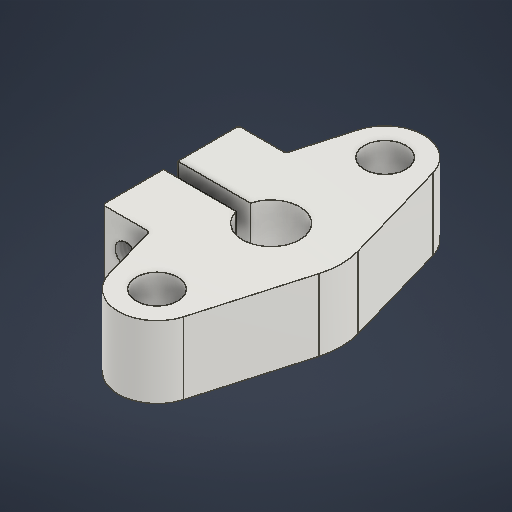
# Autodesk Inventor part: 8PI ShaftEnd Holder
Saved by Autodesk Inventor 2026.2 (Build 302298010, 298A)
## iProperties
Created: 2026-05-07
Part Number: 8PI ShaftEnd Holder
Material: 강철, 가공됨
Document SubType Name: Modeling
Designer: work
Density: 7.85 g/cm^3
Appearance: 강철
Author: work
Autodesk Inventor part; units mm, degrees
ref_plane "YZ Plane" through (0, 0, 0) normal (1, 0, 0) x (0, 1, 0)
ref_plane "XZ Plane" through (0, 0, 0) normal (0, 1, 0) x (-1, 0, 0)
ref_plane "XY Plane" through (0, 0, 0) normal (0, 0, 1) x (1, 0, 0)
sketch "스케치1" plane through (0, 0, 0) normal (0, 1, 0) x (-1, 0, 0)
  circle A0 centre (0, 0) radius 4
  line L0 (14, 9.5) -> (0, 9.5)
  line L1 (0, 9.5) -> (0, -9.5) construction
  line L2 (0, -9.5) -> (14, -9.5)
  line L3 (14, -9.5) -> (14, 9.5)
  line L4 (0, 0) -> (14, 0) construction
  line L5 (14, -1) -> (0, -1)
  line L6 (0, -1) -> (0, 1)
  line L7 (0, 1) -> (14, 1)
  line L8 (14, 1) -> (14, -1)
  line L9 (0, 0) -> (0, -15.9) construction
  circle A1 centre (0, -15.9) radius 2.9
  circle A2 centre (0, -15.9) radius 5.4
  circle A3 centre (0, 0) radius 9.8
  line L10 (-9.4173, -2.7119) -> (-5.1891, -17.3943)
  line L11 (9.4173, -2.7119) -> (5.1891, -17.3943)
  line L12 (0, 0) -> (0, 15.9) construction
  circle A4 centre (0, 15.9) radius 2.9
  circle A5 centre (0, 15.9) radius 5.4
  line L13 (-9.4173, 2.7119) -> (-5.1891, 17.3943)
  line L14 (9.4173, 2.7119) -> (5.1891, 17.3943)
  point P0 (3.873, -1)
  point P1 (3.873, 1)
  point P2 (7.4625, 9.5)
  point P3 (7.4625, -9.5)
  dimension "d0" = 8
  dimension "d1" = 19
  dimension "d2" = 10
  dimension "d3" = 2
  dimension "d4" = 5.8
  dimension "d5" = 2.5
  dimension "d6" = 5.8
  dimension "d7" = 26
  constraints: 30 end point, 9 symmetric about line, 7 coincident, 4 midpoint, 4 parallel, 3 centre point, 3 horizontal, 2 perpendicular, 1 vertical, 12 other
  measures "d0" diameter of A0
  measures "d1" distance of L1.end L0.end
  measures "d2" distance edge to line of A0 L3
  measures "d3" distance of L5.end L6.end
  measures "d4" diameter of A1
extrude "돌출1" add sketch "스케치1" along normal blind 10 contours A0 L5 A3 L7 | A3 L14 L0 L3 L7 | L5 L3 L2 L11 A3 | A3 L0 L14 | L11 L2 A3 | A3 L13 A5 L14 L0 | L2 L11 A2 L10 A3 | A5 | A2 picked at (-6.323, 4.6019)
sketch "스케치2" plane through (-14, 0, 9.5) normal (0, 0, 1) x (1, 0, 0)
  line L0 (0, 0) -> (6.5375, 0) projected
  line L1 (6.5375, 0) -> (6.5375, 10) projected
  line L2 (0, 10) -> (6.5375, 10) projected
  line L3 (0, 0) -> (0, 10) projected
  line L4 (3.2688, 0) -> (3.2688, 10) construction
  circle A0 centre (3.2688, 5.6) radius 1.5
  line L5 (0, 10) -> (6.5375, 10) projected
  point P0 (14, 0)
  dimension "d10" = 3
  dimension "d11" = 4.4
  constraints: 3 midpoint, 2 end point, 1 centre point, 1 point on line
  measures "d10" diameter of A0
  measures "d11" distance of A0.centre point (3.269, 10)
extrude "돌출2" cut sketch "스케치2" against normal through all contours A0
thread "스레드1" size "M3x0.5" class "6H" standard "ANSI Metric M Profile" full length
chamfer "모따기1" distance 0.25 angle 45 4 edges at (-7.4625, 5, 9.5) (-14, 5, 9.5) (-14, 5, -9.5) (-7.4625, 5, -9.5)
